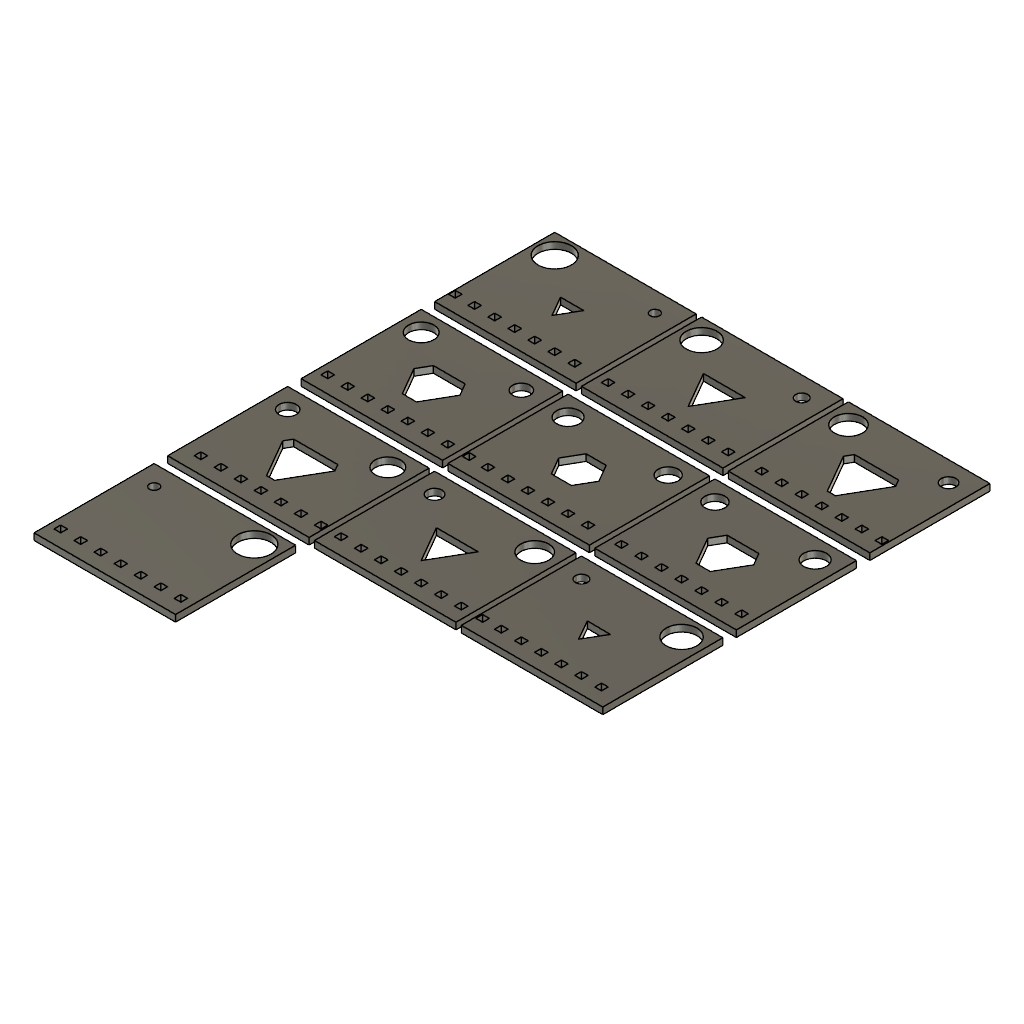
Acrylic Pieces NEW (Autodesk Fusion 360 design; units mm, degrees)
Autodesk Fusion 360 part; units mm, degrees
sketch "Sketch1" plane through (0, 0, 0) normal (0, 0, 1) x (1, 0, 0)
  line L0 (0, 0) -> (106, 0)
  line L1 (106, 0) -> (106, 90)
  line L2 (106, 90) -> (0, 90)
  line L3 (0, 90) -> (0, 0)
  line L4 (0, 0) -> (0, 10) construction
  line L5 (0, 10) -> (106, 10) construction
  line L6 (0, 45) -> (106, 45) construction
  line L7 (53, 90) -> (53, 0) construction
  line L8 (0, 15) -> (0, 10)
  line L9 (15, 10) -> (20, 10)
  line L10 (20, 10) -> (20, 15)
  line L11 (20, 15) -> (15, 15)
  line L12 (15, 15) -> (15, 10)
  line L13 (30, 10) -> (35, 10)
  line L14 (35, 10) -> (35, 15)
  line L15 (35, 15) -> (30, 15)
  line L16 (30, 15) -> (30, 10)
  line L17 (45, 10) -> (50, 10)
  line L18 (50, 10) -> (50, 15)
  line L19 (50, 15) -> (45, 15)
  line L20 (45, 15) -> (45, 10)
  line L21 (60, 10) -> (65, 10)
  line L22 (65, 10) -> (65, 15)
  line L23 (65, 15) -> (60, 15)
  line L24 (60, 15) -> (60, 10)
  line L25 (75, 10) -> (80, 10)
  line L26 (80, 10) -> (80, 15)
  line L27 (80, 15) -> (75, 15)
  line L28 (75, 15) -> (75, 10)
  line L29 (90, 10) -> (95, 10)
  line L30 (95, 10) -> (95, 15)
  line L31 (95, 15) -> (90, 15)
  line L32 (90, 15) -> (90, 10)
  circle A0 centre (15, 75) radius 12.5
  circle A1 centre (90, 75) radius 3.5
  line L33 (106, 90) -> (106, 0)
  line L34 (106, 0) -> (106, 10) construction
  line L35 (106, 15) -> (106, 10)
  line L36 (110, 45) -> (216, 45) construction
  line L37 (110, 0) -> (216, 0)
  line L38 (216, 90) -> (216, 0)
  circle A2 centre (200, 75) radius 4.5
  circle A3 centre (125, 75) radius 11.5
  line L39 (216, 90) -> (110, 90)
  line L40 (110, 6.9814) -> (216, 6.9814) construction
  line L41 (110, 0) -> (110, 6.9814) construction
  line L42 (216, 15) -> (216, 10)
  line L43 (163, 90) -> (163, 0) construction
  line L44 (216, 0) -> (216, 10) construction
  line L45 (110, 15) -> (110, 6.9814)
  line L46 (216, 0) -> (216, 90)
  line L47 (110, 90) -> (110, 0)
  line L48 (220, 10) -> (326, 10) construction
  line L49 (220, 0) -> (220, 10) construction
  line L50 (220, 15) -> (220, 10)
  line L51 (326, 15) -> (326, 10)
  line L52 (326, 0) -> (326, 10) construction
  line L53 (326, 0) -> (326, 90)
  line L54 (326, 90) -> (326, 0)
  line L55 (326, 90) -> (220, 90)
  circle A4 centre (310, 75) radius 5.5
  line L56 (220, 90) -> (220, 0)
  line L57 (273, 90) -> (273, 0) construction
  line L58 (220, 45) -> (326, 45) construction
  line L59 (220, 0) -> (326, 0)
  circle A5 centre (235, 75) radius 10.5
  line L60 (230, 10) -> (235, 10)
  line L61 (235, 10) -> (235, 15)
  line L62 (235, 15) -> (230, 15)
  line L63 (230, 15) -> (230, 10)
  line L64 (245, 10) -> (250, 10)
  line L65 (250, 10) -> (250, 15)
  line L66 (250, 15) -> (245, 15)
  line L67 (245, 15) -> (245, 10)
  line L68 (260, 10) -> (265, 10)
  line L69 (265, 10) -> (265, 15)
  line L70 (265, 15) -> (260, 15)
  line L71 (260, 15) -> (260, 10)
  line L72 (275, 10) -> (280, 10)
  line L73 (280, 10) -> (280, 15)
  line L74 (280, 15) -> (275, 15)
  line L75 (275, 15) -> (275, 10)
  line L76 (290, 10) -> (295, 10)
  line L77 (295, 10) -> (295, 15)
  line L78 (295, 15) -> (290, 15)
  line L79 (290, 15) -> (290, 10)
  line L80 (305, 10) -> (310, 10)
  line L81 (310, 10) -> (310, 15)
  line L82 (310, 15) -> (305, 15)
  line L83 (305, 15) -> (305, 10)
  line L84 (320, 10) -> (325, 10)
  line L85 (325, 10) -> (325, 15)
  line L86 (325, 15) -> (320, 15)
  line L87 (320, 15) -> (320, 10)
  line L88 (220, -100) -> (220, -90) construction
  line L89 (326, -100) -> (326, -90) construction
  line L90 (220, -85) -> (220, -90)
  line L91 (326, -85) -> (326, -90)
  line L92 (220, -100) -> (326, -100)
  line L93 (53, -10) -> (53, -100) construction
  line L94 (163, -10) -> (163, -100) construction
  circle A6 centre (125, -25) radius 8.5
  line L95 (0, -85) -> (0, -90)
  line L96 (110, -93.0186) -> (216, -93.0186) construction
  line L97 (0, -90) -> (106, -90) construction
  circle A7 centre (15, -25) radius 9.5
  line L98 (0, -100) -> (0, -90) construction
  line L99 (220, -90) -> (326, -90) construction
  line L100 (216, -100) -> (216, -90) construction
  line L101 (110, -85) -> (110, -93.0186)
  line L102 (106, -100) -> (106, -90) construction
  line L103 (326, -10) -> (220, -10)
  line L104 (106, -100) -> (106, -10)
  line L105 (273, -10) -> (273, -100) construction
  line L106 (110, -10) -> (110, -100)
  circle A8 centre (310, -25) radius 8.5
  line L107 (326, -10) -> (326, -100)
  line L108 (110, -100) -> (216, -100)
  line L109 (0, -100) -> (106, -100)
  line L110 (220, -10) -> (220, -100)
  line L111 (110, -55) -> (216, -55) construction
  circle A9 centre (235, -25) radius 7.5
  line L112 (216, -10) -> (216, -100)
  circle A10 centre (200, -25) radius 7.5
  line L113 (216, -85) -> (216, -90)
  line L114 (110, -100) -> (110, -93.0186) construction
  line L115 (106, -85) -> (106, -90)
  line L116 (106, -10) -> (106, -100)
  line L117 (0, -55) -> (106, -55) construction
  line L118 (216, -100) -> (216, -10)
  line L119 (216, -10) -> (110, -10)
  circle A11 centre (90, -25) radius 6.5
  line L120 (106, -10) -> (0, -10)
  line L121 (220, -55) -> (326, -55) construction
  line L122 (0, -10) -> (0, -100)
  line L123 (326, -100) -> (326, -10)
  circle A12 centre (235, -125) radius 4.5
  line L124 (220, -110) -> (220, -200)
  line L125 (0, -200) -> (0, -190) construction
  line L126 (0, -200) -> (106, -200)
  line L127 (106, -110) -> (0, -110)
  line L128 (110, -193.0186) -> (216, -193.0186) construction
  line L129 (110, -155) -> (216, -155) construction
  line L130 (0, -190) -> (106, -190) construction
  line L131 (0, -155) -> (106, -155) construction
  circle A13 centre (125, -125) radius 5.5
  line L132 (216, -110) -> (110, -110)
  line L133 (220, -200) -> (220, -190) construction
  line L134 (106, -200) -> (106, -190) construction
  line L135 (110, -110) -> (110, -200)
  line L136 (220, -155) -> (326, -155) construction
  line L137 (326, -110) -> (220, -110)
  line L138 (106, -185) -> (106, -190)
  line L139 (216, -200) -> (216, -190) construction
  circle A14 centre (200, -125) radius 10.5
  line L140 (106, -110) -> (106, -200)
  line L141 (326, -185) -> (326, -190)
  line L142 (326, -110) -> (326, -200)
  line L143 (106, -200) -> (106, -110)
  line L144 (326, -200) -> (326, -190) construction
  line L145 (216, -110) -> (216, -200)
  line L146 (110, -200) -> (110, -193.0186) construction
  line L147 (273, -110) -> (273, -200) construction
  line L148 (326, -200) -> (326, -110)
  line L149 (110, -185) -> (110, -193.0186)
  line L150 (216, -185) -> (216, -190)
  line L151 (216, -200) -> (216, -110)
  line L152 (163, -110) -> (163, -200) construction
  line L153 (110, -200) -> (216, -200)
  line L154 (0, -185) -> (0, -190)
  line L155 (53, -110) -> (53, -200) construction
  line L156 (220, -185) -> (220, -190)
  circle A15 centre (90, -125) radius 9.5
  line L157 (0, -110) -> (0, -200)
  circle A16 centre (310, -125) radius 11.5
  circle A17 centre (15, -125) radius 6.5
  line L158 (220, -190) -> (326, -190) construction
  line L159 (220, -200) -> (326, -200)
  circle A18 centre (90, -225) radius 12.5
  line L160 (106, -300) -> (106, -290) construction
  line L161 (0, -290) -> (106, -290) construction
  line L162 (0, -255) -> (106, -255) construction
  line L163 (0, -300) -> (106, -300)
  line L164 (106, -210) -> (0, -210)
  line L165 (106, -285) -> (106, -290)
  line L166 (53, -210) -> (53, -300) construction
  line L167 (106, -300) -> (106, -210)
  line L168 (0, -210) -> (0, -300)
  line L169 (106, -210) -> (106, -300)
  line L170 (0, -285) -> (0, -290)
  line L171 (0, -300) -> (0, -290) construction
  circle A19 centre (15, -225) radius 3.5
  line L172 (44.3397, 50) -> (53, 35)
  line L173 (53, 35) -> (61.6603, 50)
  line L174 (61.6603, 50) -> (44.3397, 50)
  line L175 (147.4115, 54) -> (163, 27)
  line L176 (163, 27) -> (178.5885, 54)
  line L177 (178.5885, 54) -> (147.4115, 54)
  line L178 (250.4833, 58) -> (273, 19)
  line L179 (273, 19) -> (295.5167, 58)
  line L180 (295.5167, 58) -> (250.4833, 58)
  line L181 (292.5083, 52.7894) -> (289.5, 58)
  line L182 (292.5083, 52.7894) -> (298.3979, 52.7894) construction
  line L183 (256.5, 58) -> (253.4917, 52.7894)
  line L184 (269.9917, 24.2106) -> (276.0083, 24.2106)
  line L185 (292.5083, 52.7894) -> (289.5, 58)
  line L186 (273, 19) -> (295.5167, 58)
  line L187 (269.9917, 24.2106) -> (276.0083, 24.2106)
  line L188 (256.5, 58) -> (253.4917, 52.7894)
  line L189 (250.4833, 58) -> (273, 19)
  line L190 (295.5167, 58) -> (250.4833, 58)
  line L191 (30.4833, -42) -> (53, -81)
  line L192 (53, -81) -> (75.5167, -42)
  line L193 (75.5167, -42) -> (30.4833, -42)
  line L194 (64.8908, -42) -> (70.2037, -51.2023)
  line L195 (64.8908, -42) -> (75.5167, -42) construction
  line L196 (35.7963, -51.2023) -> (41.1092, -42)
  line L197 (58.3129, -71.7977) -> (47.6871, -71.7977)
  line L198 (155.4944, -42) -> (147.9889, -55)
  line L199 (147.9889, -55) -> (155.4944, -68)
  line L200 (155.4944, -68) -> (170.5056, -68)
  line L201 (170.5056, -68) -> (178.0111, -55)
  line L202 (178.0111, -55) -> (170.5056, -42)
  line L203 (170.5056, -42) -> (155.4944, -42)
  line L204 (273, -81) -> (295.5167, -42)
  line L205 (255.7963, -51.2023) -> (261.1092, -42)
  line L206 (284.8908, -42) -> (295.5167, -42) construction
  line L207 (295.5167, -42) -> (250.4833, -42)
  line L208 (278.3129, -71.7977) -> (267.6871, -71.7977)
  line L209 (284.8908, -42) -> (290.2037, -51.2023)
  line L210 (250.4833, -42) -> (273, -81)
  line L211 (36.5, -142) -> (33.4917, -147.2106)
  line L212 (53, -181) -> (75.5167, -142)
  line L213 (30.4833, -142) -> (53, -181)
  line L214 (53, -181) -> (75.5167, -142)
  line L215 (30.4833, -142) -> (53, -181)
  line L216 (72.5083, -147.2106) -> (69.5, -142)
  line L217 (49.9917, -175.7894) -> (56.0083, -175.7894)
  line L218 (49.9917, -175.7894) -> (56.0083, -175.7894)
  line L219 (36.5, -142) -> (33.4917, -147.2106)
  line L220 (75.5167, -142) -> (30.4833, -142)
  line L221 (72.5083, -147.2106) -> (69.5, -142)
  line L222 (75.5167, -142) -> (30.4833, -142)
  line L223 (72.5083, -147.2106) -> (78.3979, -147.2106) construction
  line L224 (147.4115, -146) -> (163, -173)
  line L225 (163, -173) -> (178.5885, -146)
  line L226 (178.5885, -146) -> (147.4115, -146)
  line L227 (264.3938, -149.9074) -> (272.8928, -164.9994)
  line L228 (272.8928, -164.9994) -> (281.7134, -150.0931)
  line L229 (281.7134, -150.0931) -> (264.3938, -149.9074)
  line L230 (5, -90) -> (10, -90)
  line L231 (10, -90) -> (10, -85)
  line L232 (10, -85) -> (5, -85)
  line L233 (5, -85) -> (5, -90)
  line L234 (20, -90) -> (25, -90)
  line L235 (25, -90) -> (25, -85)
  line L236 (25, -85) -> (20, -85)
  line L237 (20, -85) -> (20, -90)
  line L238 (35, -90) -> (40, -90)
  line L239 (40, -90) -> (40, -85)
  line L240 (40, -85) -> (35, -85)
  line L241 (35, -85) -> (35, -90)
  line L242 (50, -90) -> (55, -90)
  line L243 (55, -90) -> (55, -85)
  line L244 (55, -85) -> (50, -85)
  line L245 (50, -85) -> (50, -90)
  line L246 (65, -90) -> (70, -90)
  line L247 (70, -90) -> (70, -85)
  line L248 (70, -85) -> (65, -85)
  line L249 (65, -85) -> (65, -90)
  line L250 (80, -90) -> (85, -90)
  line L251 (85, -90) -> (85, -85)
  line L252 (85, -85) -> (80, -85)
  line L253 (80, -85) -> (80, -90)
  line L254 (95, -90) -> (100, -90)
  line L255 (100, -90) -> (100, -85)
  line L256 (100, -85) -> (95, -85)
  line L257 (95, -85) -> (95, -90)
  line L258 (115, 10) -> (120, 10)
  line L259 (120, 10) -> (120, 15)
  line L260 (120, 15) -> (115, 15)
  line L261 (115, 15) -> (115, 10)
  line L262 (130, 10) -> (135, 10)
  line L263 (135, 10) -> (135, 15)
  line L264 (135, 15) -> (130, 15)
  line L265 (130, 15) -> (130, 10)
  line L266 (145, 10) -> (150, 10)
  line L267 (150, 10) -> (150, 15)
  line L268 (150, 15) -> (145, 15)
  line L269 (145, 15) -> (145, 10)
  line L270 (160, 10) -> (165, 10)
  line L271 (165, 10) -> (165, 15)
  line L272 (165, 15) -> (160, 15)
  line L273 (160, 15) -> (160, 10)
  line L274 (175, 10) -> (180, 10)
  line L275 (180, 10) -> (180, 15)
  line L276 (180, 15) -> (175, 15)
  line L277 (175, 15) -> (175, 10)
  line L278 (190, 10) -> (195, 10)
  line L279 (195, 10) -> (195, 15)
  line L280 (195, 15) -> (190, 15)
  line L281 (190, 15) -> (190, 10)
  line L282 (205, 10) -> (210, 10)
  line L283 (210, 10) -> (210, 15)
  line L284 (210, 15) -> (205, 15)
  line L285 (205, 15) -> (205, 10)
  line L286 (110, -90) -> (110, -85)
  line L287 (125, -85) -> (130, -85)
  line L288 (130, -85) -> (130, -90)
  line L289 (130, -90) -> (125, -90)
  line L290 (125, -90) -> (125, -85)
  line L291 (140, -85) -> (145, -85)
  line L292 (145, -85) -> (145, -90)
  line L293 (145, -90) -> (140, -90)
  line L294 (140, -90) -> (140, -85)
  line L295 (155, -85) -> (160, -85)
  line L296 (160, -85) -> (160, -90)
  line L297 (160, -90) -> (155, -90)
  line L298 (155, -90) -> (155, -85)
  line L299 (170, -85) -> (175, -85)
  line L300 (175, -85) -> (175, -90)
  line L301 (175, -90) -> (170, -90)
  line L302 (170, -90) -> (170, -85)
  line L303 (185, -85) -> (190, -85)
  line L304 (190, -85) -> (190, -90)
  line L305 (190, -90) -> (185, -90)
  line L306 (185, -90) -> (185, -85)
  line L307 (200, -85) -> (205, -85)
  line L308 (205, -85) -> (205, -90)
  line L309 (205, -90) -> (200, -90)
  line L310 (200, -90) -> (200, -85)
  line L311 (225, -90) -> (230, -90)
  line L312 (230, -90) -> (230, -85)
  line L313 (230, -85) -> (225, -85)
  line L314 (225, -85) -> (225, -90)
  line L315 (240, -90) -> (245, -90)
  line L316 (245, -90) -> (245, -85)
  line L317 (245, -85) -> (240, -85)
  line L318 (240, -85) -> (240, -90)
  line L319 (255, -90) -> (260, -90)
  line L320 (260, -90) -> (260, -85)
  line L321 (260, -85) -> (255, -85)
  line L322 (255, -85) -> (255, -90)
  line L323 (270, -90) -> (275, -90)
  line L324 (275, -90) -> (275, -85)
  line L325 (275, -85) -> (270, -85)
  line L326 (270, -85) -> (270, -90)
  line L327 (285, -90) -> (290, -90)
  line L328 (290, -90) -> (290, -85)
  line L329 (290, -85) -> (285, -85)
  line L330 (285, -85) -> (285, -90)
  line L331 (300, -90) -> (305, -90)
  line L332 (305, -90) -> (305, -85)
  line L333 (305, -85) -> (300, -85)
  line L334 (300, -85) -> (300, -90)
  line L335 (315, -90) -> (320, -90)
  line L336 (320, -90) -> (320, -85)
  line L337 (320, -85) -> (315, -85)
  line L338 (315, -85) -> (315, -90)
  line L339 (10, -190) -> (15, -190)
  line L340 (15, -190) -> (15, -185)
  line L341 (15, -185) -> (10, -185)
  line L342 (10, -185) -> (10, -190)
  line L343 (25, -190) -> (30, -190)
  line L344 (30, -190) -> (30, -185)
  line L345 (30, -185) -> (25, -185)
  line L346 (25, -185) -> (25, -190)
  line L347 (40, -190) -> (45, -190)
  line L348 (45, -190) -> (45, -185)
  line L349 (45, -185) -> (40, -185)
  line L350 (40, -185) -> (40, -190)
  line L351 (55, -190) -> (60, -190)
  line L352 (60, -190) -> (60, -185)
  line L353 (60, -185) -> (55, -185)
  line L354 (55, -185) -> (55, -190)
  line L355 (70, -190) -> (75, -190)
  line L356 (75, -190) -> (75, -185)
  line L357 (75, -185) -> (70, -185)
  line L358 (70, -185) -> (70, -190)
  line L359 (85, -190) -> (90, -190)
  line L360 (90, -190) -> (90, -185)
  line L361 (90, -185) -> (85, -185)
  line L362 (85, -185) -> (85, -190)
  line L363 (100, -190) -> (105, -190)
  line L364 (105, -190) -> (105, -185)
  line L365 (105, -185) -> (100, -185)
  line L366 (100, -185) -> (100, -190)
  line L367 (115, -185) -> (120, -185)
  line L368 (120, -185) -> (120, -190)
  line L369 (120, -190) -> (115, -190)
  line L370 (115, -190) -> (115, -185)
  line L371 (130, -185) -> (135, -185)
  line L372 (135, -185) -> (135, -190)
  line L373 (135, -190) -> (130, -190)
  line L374 (130, -190) -> (130, -185)
  line L375 (145, -185) -> (150, -185)
  line L376 (150, -185) -> (150, -190)
  line L377 (150, -190) -> (145, -190)
  line L378 (145, -190) -> (145, -185)
  line L379 (160, -185) -> (165, -185)
  line L380 (165, -185) -> (165, -190)
  line L381 (165, -190) -> (160, -190)
  line L382 (160, -190) -> (160, -185)
  line L383 (175, -185) -> (180, -185)
  line L384 (180, -185) -> (180, -190)
  line L385 (180, -190) -> (175, -190)
  line L386 (175, -190) -> (175, -185)
  line L387 (190, -185) -> (195, -185)
  line L388 (195, -185) -> (195, -190)
  line L389 (195, -190) -> (190, -190)
  line L390 (190, -190) -> (190, -185)
  line L391 (205, -185) -> (210, -185)
  line L392 (210, -185) -> (210, -190)
  line L393 (210, -190) -> (205, -190)
  line L394 (205, -190) -> (205, -185)
  line L395 (220, -185) -> (220, -190)
  line L396 (235, -190) -> (240, -190)
  line L397 (240, -190) -> (240, -185)
  line L398 (240, -185) -> (235, -185)
  line L399 (235, -185) -> (235, -190)
  line L400 (250, -190) -> (255, -190)
  line L401 (255, -190) -> (255, -185)
  line L402 (255, -185) -> (250, -185)
  line L403 (250, -185) -> (250, -190)
  line L404 (265, -190) -> (270, -190)
  line L405 (270, -190) -> (270, -185)
  line L406 (270, -185) -> (265, -185)
  line L407 (265, -185) -> (265, -190)
  line L408 (280, -190) -> (285, -190)
  line L409 (285, -190) -> (285, -185)
  line L410 (285, -185) -> (280, -185)
  line L411 (280, -185) -> (280, -190)
  line L412 (295, -190) -> (300, -190)
  line L413 (300, -190) -> (300, -185)
  line L414 (300, -185) -> (295, -185)
  line L415 (295, -185) -> (295, -190)
  line L416 (310, -190) -> (315, -190)
  line L417 (315, -190) -> (315, -185)
  line L418 (315, -185) -> (310, -185)
  line L419 (310, -185) -> (310, -190)
  line L420 (5, -290) -> (10, -290)
  line L421 (10, -290) -> (10, -285)
  line L422 (10, -285) -> (5, -285)
  line L423 (5, -285) -> (5, -290)
  line L424 (20, -290) -> (25, -290)
  line L425 (25, -290) -> (25, -285)
  line L426 (25, -285) -> (20, -285)
  line L427 (20, -285) -> (20, -290)
  line L428 (35, -290) -> (40, -290)
  line L429 (40, -290) -> (40, -285)
  line L430 (40, -285) -> (35, -285)
  line L431 (35, -285) -> (35, -290)
  line L432 (50, -290) -> (55, -290)
  line L433 (55, -290) -> (55, -285)
  line L434 (55, -285) -> (50, -285)
  line L435 (50, -285) -> (50, -290)
  line L436 (65, -290) -> (70, -290)
  line L437 (70, -290) -> (70, -285)
  line L438 (70, -285) -> (65, -285)
  line L439 (65, -285) -> (65, -290)
  line L440 (80, -290) -> (85, -290)
  line L441 (85, -290) -> (85, -285)
  line L442 (85, -285) -> (80, -285)
  line L443 (80, -285) -> (80, -290)
  line L444 (95, -290) -> (100, -290)
  line L445 (100, -290) -> (100, -285)
  line L446 (100, -285) -> (95, -285)
  line L447 (95, -285) -> (95, -290)
  line L448 (111, -85) -> (116, -85)
  line L449 (116, -85) -> (116, -90)
  line L450 (116, -90) -> (111, -90)
  line L451 (111, -90) -> (111, -85)
  line L452 (0.5, 15) -> (5.5, 15)
  line L453 (5.5, 15) -> (5.5, 10)
  line L454 (5.5, 10) -> (0.5, 10)
  line L455 (0.5, 10) -> (0.5, 15)
  line L456 (221, -190) -> (226, -190)
  line L457 (226, -190) -> (226, -185)
  line L458 (226, -185) -> (221, -185)
  line L459 (221, -185) -> (221, -190)
  point P0 (106, 0)
  point P1 (110, 0)
  point P2 (216, 0)
  point P3 (220, 0)
  point P4 (326, 0)
  point P5 (0, -100)
  point P6 (106, -100)
  point P7 (220, -100)
  point P8 (110, -100)
  point P9 (326, -100)
  point P10 (216, -100)
  point P11 (220, -200)
  point P12 (106, -200)
  point P13 (0, -200)
  point P14 (110, -200)
  point P15 (326, -200)
  point P16 (216, -200)
  point P17 (106, -300)
  point P18 (0, -300)
  point P19 (53, 45)
  point P20 (163, 45)
  point P21 (273, 45)
  point P22 (273, 45)
  point P23 (273, 45)
  point P24 (273, 45)
  point P25 (53, -55)
  point P26 (163, -55)
  point P27 (273, -55)
  point P28 (53, -155)
  point P29 (53, -155)
  point P30 (53, -155)
  point P31 (53, -155)
  point P32 (163, -155)
  point P33 (273, -155)
  dimension "d1" = 106
  dimension "d2" = 90
  dimension "d3" = 25
  dimension "d4" = 7
  dimension "d6" = 90
  dimension "d13" = 106
  dimension "d14" = 90
  dimension "d15" = 23
  dimension "d16" = 9
  dimension "d18" = 106
  dimension "d20" = 21
  dimension "d21" = 11
  dimension "d23" = 106
  dimension "d24" = 90
  dimension "d25" = 19
  dimension "d26" = 13
  dimension "d28" = 106
  dimension "d30" = 17
  dimension "d31" = 15
  dimension "d32" = 106
  dimension "d33" = 15
  dimension "d34" = 17
  dimension "d35" = 106
  dimension "d36" = 90
  dimension "d37" = 13
  dimension "d38" = 19
  dimension "d40" = 106
  dimension "d42" = 11
  dimension "d43" = 21
  dimension "d44" = 106
  dimension "d45" = 9
  dimension "d46" = 23
  dimension "d47" = 106
  dimension "d48" = 90
  dimension "d49" = 7
  dimension "d50" = 25
  dimension "d52" = 5
  dimension "d53" = 9
  dimension "d56" = 13
  dimension "d57" = 120
  dimension "d59" = 360
  dimension "d61" = 360
  dimension "d62" = 13
  dimension "d63" = 13
  dimension "d64" = 60
  dimension "d66" = 360
  dimension "d67" = 13
  dimension "d69" = 360
  dimension "d70" = 13
  dimension "d71" = 60
  dimension "d73" = 360
  dimension "d75" = 360
  dimension "d76" = 13
  dimension "d77" = 120
  dimension "d78" = 13
  dimension "d79" = 9
  dimension "d80" = 5
  constraint horizontal L0
  constraint horizontal L2
  constraint vertical L3
  constraint coincident L0.start L3.end
  constraint coincident L3 L4.end
  constraint coincident L1 L5.end
  constraint perpendicular L1 L5
  constraint midpoint L3 L6.start
  constraint midpoint L1 L6.end
  constraint midpoint L2 L7.start
  constraint midpoint L0 L7.end
  constraint horizontal L9
  constraint vertical L10
  constraint horizontal L11
  constraint vertical L12
  constraint coincident L5 L9.start
  constraint horizontal L13
  constraint vertical L14
  constraint horizontal L15
  constraint vertical L16
  constraint coincident L5 L13.start
  constraint horizontal L17
  constraint vertical L18
  constraint horizontal L19
  constraint vertical L20
  constraint coincident L5 L17.start
  constraint horizontal L21
  constraint vertical L22
  constraint horizontal L23
  constraint vertical L24
  constraint coincident L5 L21.start
  constraint horizontal L25
  constraint vertical L26
  constraint horizontal L27
  constraint vertical L28
  constraint coincident L5 L25.start
  constraint horizontal L29
  constraint vertical L30
  constraint horizontal L31
  constraint vertical L32
  constraint coincident L5 L29.start
  constraint coincident P0 L0.end
  constraint coincident L5.end L33
  constraint horizontal L37
  constraint horizontal L39
  constraint vertical L47
  constraint coincident P1 L37.start
  constraint coincident L40.start L47
  constraint coincident L40.end L46
  constraint midpoint L36.start L47
  constraint midpoint L36.end L46
  constraint midpoint L43.start L39
  constraint midpoint L43.end L37
  constraint coincident P2 L37.end
  constraint coincident L42.end L38
  constraint horizontal L59
  constraint horizontal L55
  constraint vertical L56
  constraint coincident P3 L49.start
  constraint coincident L48.start L56
  constraint coincident L48.end L53
  constraint perpendicular L48 L53
  constraint midpoint L58.start L56
  constraint midpoint L58.end L53
  constraint midpoint L57.start L55
  constraint midpoint L57.end L59
  constraint coincident P4 L52.start
  constraint coincident L48.end L54
  constraint horizontal L60
  constraint vertical L61
  constraint horizontal L62
  constraint vertical L63
  constraint coincident L48 L60.start
  constraint horizontal L64
  constraint vertical L65
  constraint horizontal L66
  constraint vertical L67
  constraint coincident L48 L64.start
  constraint horizontal L68
  constraint vertical L69
  constraint horizontal L70
  constraint vertical L71
  constraint coincident L48 L68.start
  constraint horizontal L72
  constraint vertical L73
  constraint horizontal L74
  constraint vertical L75
  constraint coincident L48 L72.start
  constraint horizontal L76
  constraint vertical L77
  constraint horizontal L78
  constraint vertical L79
  constraint coincident L48 L76.start
  constraint horizontal L80
  constraint vertical L81
  constraint horizontal L82
  constraint vertical L83
  constraint coincident L48 L80.start
  constraint horizontal L84
  constraint vertical L85
  constraint horizontal L86
  constraint vertical L87
  constraint coincident L48 L84.start
  constraint horizontal L109
  constraint horizontal L120
  constraint vertical L122
  constraint coincident P5 L98.start
  constraint coincident L95.end L122
  constraint coincident L97.end L104
  constraint perpendicular L97 L104
  constraint midpoint L117.start L122
  constraint midpoint L117.end L104
  constraint midpoint L93.start L120
  constraint midpoint L93.end L109
  constraint coincident P6 L102.start
  constraint coincident L97.end L116
  constraint horizontal L108
  constraint horizontal L119
  constraint vertical L106
  constraint coincident P8 L106.end
  constraint coincident L96.start L106
  constraint coincident L96.end L118
  constraint midpoint L111.start L106
  constraint midpoint L111.end L118
  constraint midpoint L94.start L119
  constraint midpoint L94.end L108
  constraint coincident P10 L100.start
  constraint coincident L100.end L112
  constraint horizontal L92
  constraint horizontal L103
  constraint vertical L110
  constraint coincident P7 L88.start
  constraint coincident L88.end L110
  constraint coincident L89.end L123
  constraint midpoint L121.start L110
  constraint midpoint L121.end L123
  constraint midpoint L105.start L103
  constraint midpoint L105.end L92
  constraint coincident P9 L89.start
  constraint coincident L89.end L107
  constraint horizontal L126
  constraint horizontal L127
  constraint vertical L157
  constraint coincident P13 L125.start
  constraint coincident L125.end L157
  constraint coincident L130.end L143
  constraint perpendicular L130 L143
  constraint midpoint L131.start L157
  constraint midpoint L131.end L143
  constraint midpoint L155.start L127
  constraint midpoint L155.end L126
  constraint coincident P12 L126.end
  constraint coincident L130.end L140
  constraint horizontal L153
  constraint horizontal L132
  constraint vertical L135
  constraint coincident P14 L135.end
  constraint coincident L128.start L135
  constraint coincident L128.end L151
  constraint perpendicular L128 L151
  constraint midpoint L129.start L135
  constraint midpoint L129.end L151
  constraint midpoint L152.start L132
  constraint midpoint L152.end L153
  constraint coincident P16 L139.start
  constraint coincident L139.end L145
  constraint horizontal L159
  constraint horizontal L137
  constraint vertical L124
  constraint coincident P11 L124.end
  constraint coincident L133.end L124
  constraint coincident L141.end L148
  constraint midpoint L136.start L124
  constraint midpoint L136.end L148
  constraint midpoint L147.start L137
  constraint midpoint L147.end L159
  constraint coincident P15 L142.end
  constraint coincident L141.end L142
  constraint horizontal L163
  constraint horizontal L164
  constraint vertical L168
  constraint coincident P18 L163.start
  constraint coincident L161.start L168
  constraint coincident L160.end L167
  constraint perpendicular L161 L167
  constraint midpoint L162.start L168
  constraint midpoint L162.end L167
  constraint midpoint L166.start L164
  constraint midpoint L166.end L163
  constraint coincident P17 L160.start
  constraint coincident L160.end L169
  constraint midpoint L7 P19
  constraint midpoint L36 P20
  constraint midpoint L58 P24
  constraint coincident P24 P23
  constraint horizontal L182
  constraint coincident L179 L181.start
  constraint coincident L180 L181.end
  constraint coincident L181.start L186
  constraint coincident L181.end L190
  constraint midpoint L117 P25
  constraint horizontal L195
  constraint coincident L193 L194.start
  constraint coincident L192 L194.end
  constraint midpoint L94 P26
  constraint horizontal L206
  constraint coincident L206.start L207
  constraint coincident L209.end L204
  constraint coincident P31 P30
  constraint horizontal L223
  constraint coincident L216.start L212
  constraint coincident L216.end L220
  constraint coincident L216.start L214
  constraint coincident L216.end L222
  constraint midpoint L152 P32
  constraint midpoint L136 P33
  constraint horizontal L230
  constraint vertical L231
  constraint horizontal L232
  constraint vertical L233
  constraint coincident L97 L230.start
  constraint horizontal L234
  constraint vertical L235
  constraint horizontal L236
  constraint vertical L237
  constraint coincident L97 L234.start
  constraint horizontal L238
  constraint vertical L239
  constraint horizontal L240
  constraint vertical L241
  constraint coincident L97 L238.start
  constraint horizontal L242
  constraint vertical L243
  constraint horizontal L244
  constraint vertical L245
  constraint coincident L97 L242.start
  constraint horizontal L246
  constraint vertical L247
  constraint horizontal L248
  constraint vertical L249
  constraint coincident L97 L246.start
  constraint horizontal L250
  constraint vertical L251
  constraint horizontal L252
  constraint vertical L253
  constraint coincident L97 L250.start
  constraint horizontal L254
  constraint vertical L255
  constraint horizontal L256
  constraint vertical L257
  constraint coincident L97 L254.start
  constraint horizontal L258
  constraint vertical L259
  constraint horizontal L260
  constraint vertical L261
  constraint horizontal L262
  constraint vertical L263
  constraint horizontal L264
  constraint vertical L265
  constraint horizontal L266
  constraint vertical L267
  constraint horizontal L268
  constraint vertical L269
  constraint horizontal L270
  constraint vertical L271
  constraint horizontal L272
  constraint vertical L273
  constraint horizontal L274
  constraint vertical L275
  constraint horizontal L276
  constraint vertical L277
  constraint horizontal L278
  constraint vertical L279
  constraint horizontal L280
  constraint vertical L281
  constraint horizontal L282
  constraint vertical L283
  constraint horizontal L284
  constraint vertical L285
  constraint vertical L286
  constraint horizontal L287
  constraint vertical L288
  constraint horizontal L289
  constraint vertical L290
  constraint horizontal L291
  constraint vertical L292
  constraint horizontal L293
  constraint vertical L294
  constraint horizontal L295
  constraint vertical L296
  constraint horizontal L297
  constraint vertical L298
  constraint horizontal L299
  constraint vertical L300
  constraint horizontal L301
  constraint vertical L302
  constraint horizontal L303
  constraint vertical L304
  constraint horizontal L305
  constraint vertical L306
  constraint horizontal L307
  constraint vertical L308
  constraint horizontal L309
  constraint vertical L310
  constraint horizontal L311
  constraint vertical L312
  constraint horizontal L313
  constraint vertical L314
  constraint coincident L99 L311.start
  constraint horizontal L315
  constraint vertical L316
  constraint horizontal L317
  constraint vertical L318
  constraint coincident L99 L315.start
  constraint horizontal L319
  constraint vertical L320
  constraint horizontal L321
  constraint vertical L322
  constraint coincident L99 L319.start
  constraint horizontal L323
  constraint vertical L324
  constraint horizontal L325
  constraint vertical L326
  constraint coincident L99 L323.start
  constraint horizontal L327
  constraint vertical L328
  constraint horizontal L329
  constraint vertical L330
  constraint coincident L99 L327.start
  constraint horizontal L331
  constraint vertical L332
  constraint horizontal L333
  constraint vertical L334
  constraint coincident L99 L331.start
  constraint horizontal L335
  constraint vertical L336
  constraint horizontal L337
  constraint vertical L338
  constraint coincident L99 L335.start
  constraint horizontal L339
  constraint vertical L340
  constraint horizontal L341
  constraint vertical L342
  constraint coincident L130 L339.start
  constraint horizontal L343
  constraint vertical L344
  constraint horizontal L345
  constraint vertical L346
  constraint coincident L130 L343.start
  constraint horizontal L347
  constraint vertical L348
  constraint horizontal L349
  constraint vertical L350
  constraint coincident L130 L347.start
  constraint horizontal L351
  constraint vertical L352
  constraint horizontal L353
  constraint vertical L354
  constraint coincident L130 L351.start
  constraint horizontal L355
  constraint vertical L356
  constraint horizontal L357
  constraint vertical L358
  constraint coincident L130 L355.start
  constraint horizontal L359
  constraint vertical L360
  constraint horizontal L361
  constraint vertical L362
  constraint coincident L130 L359.start
  constraint horizontal L363
  constraint vertical L364
  constraint horizontal L365
  constraint vertical L366
  constraint coincident L130 L363.start
  constraint horizontal L367
  constraint vertical L368
  constraint horizontal L369
  constraint vertical L370
  constraint horizontal L371
  constraint vertical L372
  constraint horizontal L373
  constraint vertical L374
  constraint horizontal L375
  constraint vertical L376
  constraint horizontal L377
  constraint vertical L378
  constraint horizontal L379
  constraint vertical L380
  constraint horizontal L381
  constraint vertical L382
  constraint horizontal L383
  constraint vertical L384
  constraint horizontal L385
  constraint vertical L386
  constraint horizontal L387
  constraint vertical L388
  constraint horizontal L389
  constraint vertical L390
  constraint horizontal L391
  constraint vertical L392
  constraint horizontal L393
  constraint vertical L394
  constraint horizontal L396
  constraint vertical L397
  constraint horizontal L398
  constraint vertical L399
  constraint coincident L158 L396.start
  constraint horizontal L400
  constraint vertical L401
  constraint horizontal L402
  constraint vertical L403
  constraint coincident L158 L400.start
  constraint horizontal L404
  constraint vertical L405
  constraint horizontal L406
  constraint vertical L407
  constraint coincident L158 L404.start
  constraint horizontal L408
  constraint vertical L409
  constraint horizontal L410
  constraint vertical L411
  constraint coincident L158 L408.start
  constraint horizontal L412
  constraint vertical L413
  constraint horizontal L414
  constraint vertical L415
  constraint coincident L158 L412.start
  constraint horizontal L416
  constraint vertical L417
  constraint horizontal L418
  constraint vertical L419
  constraint coincident L158 L416.start
  constraint horizontal L420
  constraint vertical L421
  constraint horizontal L422
  constraint vertical L423
  constraint coincident L161 L420.start
  constraint horizontal L424
  constraint vertical L425
  constraint horizontal L426
  constraint vertical L427
  constraint coincident L161 L424.start
  constraint horizontal L428
  constraint vertical L429
  constraint horizontal L430
  constraint vertical L431
  constraint coincident L161 L428.start
  constraint horizontal L432
  constraint vertical L433
  constraint horizontal L434
  constraint vertical L435
  constraint coincident L161 L432.start
  constraint horizontal L436
  constraint vertical L437
  constraint horizontal L438
  constraint vertical L439
  constraint coincident L161 L436.start
  constraint horizontal L440
  constraint vertical L441
  constraint horizontal L442
  constraint vertical L443
  constraint coincident L161 L440.start
  constraint horizontal L444
  constraint vertical L445
  constraint horizontal L446
  constraint vertical L447
  constraint coincident L161 L444.start
  constraint horizontal L448
  constraint vertical L449
  constraint horizontal L450
  constraint vertical L451
  constraint horizontal L452
  constraint vertical L453
  constraint horizontal L454
  constraint vertical L455
  constraint coincident L5 L453.end
  constraint horizontal L456
  constraint vertical L457
  constraint horizontal L458
  constraint vertical L459
  constraint coincident L158 L456.start
  measures "d1" distance of L0.start P0
  measures "d2" distance of L0.start L2.end
  measures "d3" diameter of A0
  measures "d4" diameter of A1
  measures "d6" distance of L1.end P0
  measures "d13" distance of P2 P1
  measures "d14" distance of L39.end P1
  measures "d15" diameter of A3
  measures "d16" diameter of A2
  measures "d18" distance of P4 P3
  measures "d20" diameter of A5
  measures "d21" diameter of A4
  measures "d23" distance of P6 P5
  measures "d24" distance of L120.end P5
  measures "d25" diameter of A7
  measures "d26" diameter of A11
  measures "d28" distance of P10 P8
  measures "d30" diameter of A6
  measures "d31" diameter of A10
  measures "d32" distance of P7 P9
  measures "d33" diameter of A9
  measures "d34" diameter of A8
  measures "d35" distance of P12 P13
  measures "d36" distance of L127.end P13
  measures "d37" diameter of A17
  measures "d38" diameter of A15
  measures "d40" distance of P16 P14
  measures "d42" diameter of A13
  measures "d43" diameter of A14
  measures "d44" distance of P11 P15
  measures "d45" diameter of A12
  measures "d46" diameter of A16
  measures "d47" distance of P17 P18
  measures "d48" distance of L164.end P18
  measures "d49" diameter of A19
  measures "d50" diameter of A18
  measures "d52" distance of P19 L174
  measures "d53" distance of P20 L177
  measures "d56" distance of P24 L180
  measures "d57" angle of L181 L182
  measures "d62" distance of P24 L190
  measures "d63" distance of P25 L193
  measures "d64" angle of L194 L195
  measures "d67" distance of P26 L203
  measures "d70" distance of P27 L207
  measures "d71" angle of L206 L209
  measures "d76" distance of P31 L220
  measures "d77" angle of L216 L223
  measures "d78" distance of P31 L222
  measures "d79" distance of P32 L226
  measures "d80" distance of P33 L229
extrude "Extrude1" add sketch "Sketch1" along normal blind 5 contours L0 L1 L2 L3 L8 L33 L35 | L37 L38 L39 L42 L45 L46 L47 | L50 L51 L53 L54 L55 L56 L59 | L90 L91 L92 L103 L107 L110 L123 | L95 L104 L109 L115 L116 L120 L122 | L101 L106 L108 L112 L113 L118 L119 L286 | L124 L137 L141 L142 L148 L156 L159 L395 | L126 L127 L138 L140 L143 L154 L157 | L132 L135 L145 L149 L150 L151 L153 | L163 L164 L165 L167 L168 L169 L170 | L178 L180 L183 L188 L189 L190 | L178 L179 L184 L186 L187 L189 | L179 L180 L181 L185 L186 L190 | L191 L193 L196 | L191 L192 L197 | L192 L193 L194 | L204 L208 L210 | L204 L207 L209 | L205 L207 L210 | L211 L213 L215 L219 L220 L222 | L212 L214 L216 L220 L221 L222 | L212 L213 L214 L215 L217 L218 makes body 1 at (130.6668, -153.8282, 0) makes body 2 at (240.0786, -56.2271, 0) makes body 3 at (194.6416, 46.5042, 0) makes body 4 at (194.5239, -57.493, 0) makes body 5 at (246.5767, -154.7983, 0) makes body 6 at (19.0151, -154.5159, 0) makes body 7 at (307.9107, 45.8091, 0) makes body 8 at (80.4662, 45.5033, 0) makes body 9 at (85.55, -55.8464, 0) makes body 10 at (48.8766, -247.4651, 0)
